Autodesk Fusion 360 part; units mm, degrees
(part 2 of 3)
sketch "Left ribbon cover release catch outline" plane through (0, 0, 1.5) normal (0, 0, 1) x (1, 0, 0) in component "02 Flat front and ribbon cover - PRINT 1"
  line L0 (84.4, -13.8) -> (85.6, -13.8)
  line L1 (85.6, -13.8) -> (85.6, -5.8)
  line L2 (85.6, -5.8) -> (86.6, -5.8)
  line L3 (86.6, -5.8) -> (86.6, -5.2)
  line L4 (86.6, -5.2) -> (85.6, -4.8)
  line L5 (85.6, -4.8) -> (84.4, -4.8)
  line L6 (84.4, -4.8) -> (84.4, -13.8)
extrude "Left ribbon cover release catch" add sketch "Left ribbon cover release catch outline" along normal blind 5 bodies 14 in component "02 Flat front and ribbon cover - PRINT 1"
ref_plane "WorkPlane30" through (0, 0, 1.5) normal (0, 0, 1) x (1, 0, 0) in component "02 Flat front and ribbon cover - PRINT 1"
sketch "Right ribbon cover release catch outline" plane through (0, 0, 1.5) normal (0, 0, 1) x (1, 0, 0) in component "02 Flat front and ribbon cover - PRINT 1"
  line L0 (129.6, -13.8) -> (128.4, -13.8)
  line L1 (128.4, -13.8) -> (128.4, -5.8)
  line L2 (128.4, -5.8) -> (127.4, -5.8)
  line L3 (127.4, -5.8) -> (127.4, -5.2)
  line L4 (127.4, -5.2) -> (128.4, -4.8)
  line L5 (128.4, -4.8) -> (129.6, -4.8)
  line L6 (129.6, -4.8) -> (129.6, -13.8)
extrude "Right ribbon cover release catch" add sketch "Right ribbon cover release catch outline" along normal blind 5 bodies 14 in component "02 Flat front and ribbon cover - PRINT 1"
ref_plane "WorkPlane31" through (0, -16.2, 0) normal (0, 1, 0) x (0, 0, 1) in component "02 Flat front and ribbon cover - PRINT 1"
sketch "Purdue Hackers official flat logo recess 1 outline" plane through (0, -16.2, 0) normal (0, 1, 0) x (1, 0, 0) in component "02 Flat front and ribbon cover - PRINT 1"
  line L0 (101.6666, -76) -> (91, -76)
  line L1 (91, -76) -> (91, -86.2945)
  line L2 (91, -86.2945) -> (101.6666, -86.2945)
  line L3 (101.6666, -86.2945) -> (101.6666, -76)
  line L4 (101.6666, -76) -> (101.6666, -76)
extrude "Purdue Hackers official flat logo recess 1" cut sketch "Purdue Hackers official flat logo recess 1 outline" along normal blind 0.6 bodies 14 in component "02 Flat front and ribbon cover - PRINT 1"
ref_plane "WorkPlane32" through (0, -16.2, 0) normal (0, 1, 0) x (0, 0, 1) in component "02 Flat front and ribbon cover - PRINT 1"
sketch "Purdue Hackers official flat logo recess 2 outline" plane through (0, -16.2, 0) normal (0, 1, 0) x (1, 0, 0) in component "02 Flat front and ribbon cover - PRINT 1"
  line L0 (112.3334, -96.5892) -> (123, -96.5892)
  line L1 (123, -96.5892) -> (123, -76)
  line L2 (123, -76) -> (112.3334, -76)
  line L3 (112.3334, -76) -> (112.3334, -86.2945)
  line L4 (112.3334, -86.2945) -> (101.6666, -86.2945)
  line L5 (101.6666, -86.2945) -> (101.6666, -106.8837)
  line L6 (101.6666, -106.8837) -> (112.3334, -106.8837)
  line L7 (112.3334, -106.8837) -> (112.3334, -96.5892)
  line L8 (112.3334, -96.5892) -> (112.3334, -96.5892)
extrude "Purdue Hackers official flat logo recess 2" cut sketch "Purdue Hackers official flat logo recess 2 outline" along normal blind 0.6 bodies 14 in component "02 Flat front and ribbon cover - PRINT 1"
ref_plane "WorkPlane33" through (0, -16.2, 0) normal (0, 1, 0) x (0, 0, 1) in component "02 Flat front and ribbon cover - PRINT 1"
sketch "Logo corner separation for manifold print outline" plane through (0, -16.2, 0) normal (0, 1, 0) x (1, 0, 0) in component "02 Flat front and ribbon cover - PRINT 1"
  line L0 (101.6666, -86.2945) -> (101.2666, -86.2945)
  line L1 (101.2666, -86.2945) -> (101.6666, -85.8945)
  line L2 (101.6666, -85.8945) -> (101.6666, -86.2945)
extrude "Logo corner separation for manifold print" add sketch "Logo corner separation for manifold print outline" along normal blind 0.6 bodies 14 in component "02 Flat front and ribbon cover - PRINT 1"
ref_plane "WorkPlane36" through (0, 0, -9) normal (0, 0, 1) x (1, 0, 0) in component "01 Electronics case - PRINT 1"
sketch "7 mm retaining hook thickness 25 outline" plane through (0, 0, -9) normal (0, 0, 1) x (1, 0, 0) in component "01 Electronics case - PRINT 1"
  line L0 (12, -11) -> (38, -11)
  line L1 (38, -11) -> (38, 45)
  line L2 (38, 45) -> (12, 45)
  line L3 (12, 45) -> (12, -11)
extrude "7 mm retaining hook thickness 25" add sketch "7 mm retaining hook thickness 25 outline" along normal blind 2 bodies 13 in component "01 Electronics case - PRINT 1"
ref_plane "WorkPlane37" through (0, 0, -9) normal (0, 0, 1) x (1, 0, 0) in component "01 Electronics case - PRINT 1"
sketch "7 mm retaining hook thickness 189 outline" plane through (0, 0, -9) normal (0, 0, 1) x (1, 0, 0) in component "01 Electronics case - PRINT 1"
  line L0 (176, -11) -> (202, -11)
  line L1 (202, -11) -> (202, 45)
  line L2 (202, 45) -> (176, 45)
  line L3 (176, 45) -> (176, -11)
extrude "7 mm retaining hook thickness 189" add sketch "7 mm retaining hook thickness 189 outline" along normal blind 2 bodies 13 in component "01 Electronics case - PRINT 1"
fillet "Rounded retaining arm upper roots" radius 1.5 4 edges at (189, -11, 65) (25, -11, 65) (189, -6, 65) (25, -6, 65) on bodies 13 in component "01 Electronics case - PRINT 1"
fillet "Rounded retaining arm inner knees" radius 1.5 4 edges at (25, -6, 7) (189, -6, 7) (189, -1, -2) (25, -1, -2) on bodies 13 in component "01 Electronics case - PRINT 1"
fillet "Rounded retaining arm outside heels" radius 2 2 edges at (25, -11, -9) (189, -11, -9) on bodies 13 in component "01 Electronics case - PRINT 1"
fillet "Lower service cover clip root relief" radius 0.6 4 edges at (159, -14.2, 71.75) (55, -14.2, 71.75) (159, -14.2, 72.95) (55, -14.2, 72.95) on bodies 14 in component "02 Flat front and ribbon cover - PRINT 1"
fillet "Upper service cover clip root relief" radius 0.4 4 edges at (159, -14.2, 163.45) (55, -14.2, 163.45) (159, -14.2, 164.25) (55, -14.2, 164.25) on bodies 14 in component "02 Flat front and ribbon cover - PRINT 1"
ref_plane "WorkPlane38" through (0, 15.6, 0) normal (0, 1, 0) x (0, 0, 1) in component "01 Electronics case - PRINT 1"
sketch "Pi screw entry relief - 0.2 mm deep layout" plane through (0, 15.6, 0) normal (0, 1, 0) x (1, 0, 0) in component "01 Electronics case - PRINT 1"
  circle A0 centre (149.5, -78.5) radius 1.4
  circle A1 centre (198.5, -78.5) radius 1.4
  circle A2 centre (149.5, -136.5) radius 1.4
  circle A3 centre (198.5, -136.5) radius 1.4
extrude "Pi screw entry relief - 0.2 mm deep" cut sketch "Pi screw entry relief - 0.2 mm deep layout" along normal blind 0.2 bodies 13 in component "01 Electronics case - PRINT 1"
ref_plane "WorkPlane39" through (0, 0, -13.5) normal (0, 0, 1) x (1, 0, 0) in component "01 Electronics case - PRINT 1"
sketch "Camera screw entry relief - 0.2 mm deep layout" plane through (0, 0, -13.5) normal (0, 0, 1) x (1, 0, 0) in component "01 Electronics case - PRINT 1"
  circle A0 centre (117.5, -7.15) radius 1.1
  circle A1 centre (117.5, 6.35) radius 1.1
  circle A2 centre (96.5, -7.15) radius 1.1
  circle A3 centre (96.5, 6.35) radius 1.1
extrude "Camera screw entry relief - 0.2 mm deep" cut sketch "Camera screw entry relief - 0.2 mm deep layout" along normal blind 0.2 bodies 13 in component "01 Electronics case - PRINT 1"
ref_plane "WorkPlane40" through (0, 0, -50) normal (0, 0, 1) x (1, 0, 0) in component "01 Electronics case - PRINT 1"
sketch "Remove integral mount below case floor outline" plane through (0, 0, -50) normal (0, 0, 1) x (1, 0, 0) in component "01 Electronics case - PRINT 1"
  line L0 (-2, -30) -> (216, -30)
  line L1 (216, -30) -> (216, 50)
  line L2 (216, 50) -> (-2, 50)
  line L3 (-2, 50) -> (-2, -30)
extrude "Remove integral mount below case floor" cut sketch "Remove integral mount below case floor outline" along normal blind 119 bodies 13 in component "01 Electronics case - PRINT 1"
ref_plane "WorkPlane41" through (0, 0, 69) normal (0, 0, 1) x (1, 0, 0) in component "01 Electronics case - PRINT 1"
sketch "Restore flat mounting floor 25 outline" plane through (0, 0, 69) normal (0, 0, 1) x (1, 0, 0) in component "01 Electronics case - PRINT 1"
  line L0 (15, 13) -> (35, 13)
  line L1 (35, 13) -> (35, 22)
  line L2 (35, 22) -> (15, 22)
  line L3 (15, 22) -> (15, 13)
extrude "Restore flat mounting floor 25" add sketch "Restore flat mounting floor 25 outline" along normal blind 0.5 bodies 13 in component "01 Electronics case - PRINT 1"
ref_plane "WorkPlane42" through (0, 0, 69) normal (0, 0, 1) x (1, 0, 0) in component "01 Electronics case - PRINT 1"
sketch "Restore flat mounting floor 189 outline" plane through (0, 0, 69) normal (0, 0, 1) x (1, 0, 0) in component "01 Electronics case - PRINT 1"
  line L0 (179, 13) -> (199, 13)
  line L1 (199, 13) -> (199, 22)
  line L2 (199, 22) -> (179, 22)
  line L3 (179, 22) -> (179, 13)
extrude "Restore flat mounting floor 189" add sketch "Restore flat mounting floor 189 outline" along normal blind 0.5 bodies 13 in component "01 Electronics case - PRINT 1"
ref_plane "WorkPlane43" through (0, 0, 71.4) normal (0, 0, 1) x (1, 0, 0) in component "01 Electronics case - PRINT 1"
sketch "Remove obsolete camera-root stub outline" plane through (0, 0, 71.4) normal (0, 0, 1) x (1, 0, 0) in component "01 Electronics case - PRINT 1"
  line L0 (85.99, -11.01) -> (128.01, -11.01)
  line L1 (128.01, -11.01) -> (128.01, -4.99)
  line L2 (128.01, -4.99) -> (85.99, -4.99)
  line L3 (85.99, -4.99) -> (85.99, -11.01)
extrude "Remove obsolete camera-root stub" cut sketch "Remove obsolete camera-root stub outline" along normal blind 0.71 bodies 13 in component "01 Electronics case - PRINT 1"
ref_plane "WorkPlane44" through (0, 0, 68.9) normal (0, 0, 1) x (1, 0, 0) in component "01 Electronics case - PRINT 1"
sketch "Six M3 bench assembly clearance holes layout" plane through (0, 0, 68.9) normal (0, 0, 1) x (1, 0, 0) in component "01 Electronics case - PRINT 1"
  circle A0 centre (18, 16) radius 1.7
  circle A1 centre (32, 16) radius 1.7
  circle A2 centre (182, 16) radius 1.7
  circle A3 centre (196, 16) radius 1.7
  circle A4 centre (92, -2.5) radius 1.7
  circle A5 centre (122, -2.5) radius 1.7
extrude "Six M3 bench assembly clearance holes" cut sketch "Six M3 bench assembly clearance holes layout" along normal blind 2.6 bodies 13 in component "01 Electronics case - PRINT 1"
ref_plane "WorkPlane45" through (0, 0, 75) normal (0, 0, 1) x (1, 0, 0) in component "01 Electronics case - PRINT 1"
sketch "Battery port open to front edge outline" plane through (0, 0, 75) normal (0, 0, 1) x (1, 0, 0) in component "01 Electronics case - PRINT 1"
  line L0 (-1, -14.1) -> (3.2, -14.1)
  line L1 (3.2, -14.1) -> (3.2, 20.5)
  line L2 (3.2, 20.5) -> (-1, 20.5)
  line L3 (-1, 20.5) -> (-1, -14.1)
extrude "Battery port open to front edge" cut sketch "Battery port open to front edge outline" along normal blind 77 bodies 13 in component "01 Electronics case - PRINT 1"
ref_plane "WorkPlane46" through (0, 0, 77) normal (0, 0, 1) x (1, 0, 0) in component "01 Electronics case - PRINT 1"
sketch "Pi side ports open to front edge outline" plane through (0, 0, 77) normal (0, 0, 1) x (1, 0, 0) in component "01 Electronics case - PRINT 1"
  line L0 (210.8, -14.1) -> (215, -14.1)
  line L1 (215, -14.1) -> (215, 18)
  line L2 (215, 18) -> (210.8, 18)
  line L3 (210.8, 18) -> (210.8, -14.1)
extrude "Pi side ports open to front edge" cut sketch "Pi side ports open to front edge outline" along normal blind 60 bodies 13 in component "01 Electronics case - PRINT 1"
ref_plane "WorkPlane47" through (0, 0, 164.5) normal (0, 0, 1) x (1, 0, 0) in component "01 Electronics case - PRINT 1"
sketch "Pi top ports open to front edge outline" plane through (0, 0, 164.5) normal (0, 0, 1) x (1, 0, 0) in component "01 Electronics case - PRINT 1"
  line L0 (144, -14.1) -> (203, -14.1)
  line L1 (203, -14.1) -> (203, 17)
  line L2 (203, 17) -> (144, 17)
  line L3 (144, 17) -> (144, -14.1)
extrude "Pi top ports open to front edge" cut sketch "Pi top ports open to front edge outline" along normal blind 2.6 bodies 13 in component "01 Electronics case - PRINT 1"
ref_plane "WorkPlane48" through (0, 0, 164.5) normal (0, 0, 1) x (1, 0, 0) in component "01 Electronics case - PRINT 1"
sketch "Relocated upper-right cover latch outline" plane through (0, 0, 164.5) normal (0, 0, 1) x (1, 0, 0) in component "01 Electronics case - PRINT 1"
  line L0 (205, -10) -> (211, -10)
  line L1 (211, -10) -> (211, -5.5)
  line L2 (211, -5.5) -> (205, -5.5)
  line L3 (205, -5.5) -> (205, -10)
extrude "Relocated upper-right cover latch" cut sketch "Relocated upper-right cover latch outline" along normal blind 2.6 bodies 13 in component "01 Electronics case - PRINT 1"
ref_plane "WorkPlane49" through (0, 0, 161) normal (0, 0, 1) x (1, 0, 0) in component "01 Electronics case - PRINT 1"
sketch "Reinforced 6 mm roof tether bridge outline" plane through (0, 0, 161) normal (0, 0, 1) x (1, 0, 0) in component "01 Electronics case - PRINT 1"
  line L0 (96, -4) -> (120, -4)
  line L1 (120, -4) -> (120, 14)
  line L2 (120, 14) -> (96, 14)
  line L3 (96, 14) -> (96, -4)
extrude "Reinforced 6 mm roof tether bridge" add sketch "Reinforced 6 mm roof tether bridge outline" along normal blind 6 bodies 13 in component "01 Electronics case - PRINT 1"
ref_plane "WorkPlane50" through (0, 0, 160.9) normal (0, 0, 1) x (1, 0, 0) in component "01 Electronics case - PRINT 1"
sketch "Two accessible roof tether slots layout" plane through (0, 0, 160.9) normal (0, 0, 1) x (1, 0, 0) in component "01 Electronics case - PRINT 1"
  line L0 (99, 1) -> (104, 1)
  line L1 (104, 1) -> (104, 8)
  line L2 (104, 8) -> (99, 8)
  line L3 (99, 8) -> (99, 1)
  line L4 (112, 1) -> (117, 1)
  line L5 (117, 1) -> (117, 8)
  line L6 (117, 8) -> (112, 8)
  line L7 (112, 8) -> (112, 1)
extrude "Two accessible roof tether slots" cut sketch "Two accessible roof tether slots layout" along normal blind 6.2 bodies 13 in component "01 Electronics case - PRINT 1"
ref_plane "WorkPlane34" through (0, 0, -12.5) normal (0, 0, 1) x (1, 0, 0) in component "02 Flat front and ribbon cover - PRINT 1"
sketch "Continuous flat ribbon-cover exterior outline" plane through (0, 0, -12.5) normal (0, 0, 1) x (1, 0, 0) in component "02 Flat front and ribbon cover - PRINT 1"
  line L0 (96, -16.2) -> (118, -16.2)
  line L1 (118, -16.2) -> (118, -12.6)
  line L2 (118, -12.6) -> (96, -12.6)
  line L3 (96, -12.6) -> (96, -16.2)
extrude "Continuous flat ribbon-cover exterior" add sketch "Continuous flat ribbon-cover exterior outline" along normal blind 86.8 bodies 14 in component "02 Flat front and ribbon cover - PRINT 1"
ref_plane "WorkPlane35" through (0, 0, 1) normal (0, 0, 1) x (1, 0, 0) in component "02 Flat front and ribbon cover - PRINT 1"
sketch "Flat base beneath lower release bridge outline" plane through (0, 0, 1) normal (0, 0, 1) x (1, 0, 0) in component "02 Flat front and ribbon cover - PRINT 1"
  line L0 (84.4, -16.2) -> (129.6, -16.2)
  line L1 (129.6, -16.2) -> (129.6, -12.6)
  line L2 (129.6, -12.6) -> (84.4, -12.6)
  line L3 (84.4, -12.6) -> (84.4, -16.2)
extrude "Flat base beneath lower release bridge" add sketch "Flat base beneath lower release bridge outline" along normal blind 6 bodies 14 in component "02 Flat front and ribbon cover - PRINT 1"
ref_plane "WorkPlane36" through (0, 0, -12.5) normal (0, 0, 1) x (1, 0, 0) in component "02 Flat front and ribbon cover - PRINT 1"
sketch "Extend ribbon edge flange 96 outline" plane through (0, 0, -12.5) normal (0, 0, 1) x (1, 0, 0) in component "02 Flat front and ribbon cover - PRINT 1"
  line L0 (96, -12.6) -> (98, -12.6)
  line L1 (98, -12.6) -> (98, -11.2)
  line L2 (98, -11.2) -> (96, -11.2)
  line L3 (96, -11.2) -> (96, -12.6)
extrude "Extend ribbon edge flange 96" add sketch "Extend ribbon edge flange 96 outline" along normal blind 8.6 bodies 14 in component "02 Flat front and ribbon cover - PRINT 1"
ref_plane "WorkPlane37" through (0, 0, -12.5) normal (0, 0, 1) x (1, 0, 0) in component "02 Flat front and ribbon cover - PRINT 1"
sketch "Extend ribbon edge flange 116 outline" plane through (0, 0, -12.5) normal (0, 0, 1) x (1, 0, 0) in component "02 Flat front and ribbon cover - PRINT 1"
  line L0 (116, -12.6) -> (118, -12.6)
  line L1 (118, -12.6) -> (118, -11.2)
  line L2 (118, -11.2) -> (116, -11.2)
  line L3 (116, -11.2) -> (116, -12.6)
extrude "Extend ribbon edge flange 116" add sketch "Extend ribbon edge flange 116 outline" along normal blind 8.6 bodies 14 in component "02 Flat front and ribbon cover - PRINT 1"
ref_plane "WorkPlane38" through (0, 0, 162.9) normal (0, 0, 1) x (1, 0, 0) in component "02 Flat front and ribbon cover - PRINT 1"
sketch "Remove old top snap over USB opening outline" plane through (0, 0, 162.9) normal (0, 0, 1) x (1, 0, 0) in component "02 Flat front and ribbon cover - PRINT 1"
  line L0 (156, -14.2) -> (162, -14.2)
  line L1 (162, -14.2) -> (162, -5.5)
  line L2 (162, -5.5) -> (156, -5.5)
  line L3 (156, -5.5) -> (156, -14.2)
extrude "Remove old top snap over USB opening" cut sketch "Remove old top snap over USB opening outline" along normal blind 2.5 bodies 14 in component "02 Flat front and ribbon cover - PRINT 1"
ref_plane "WorkPlane39" through (205.5, 0, 0) normal (1, 0, 0) x (0, 1, 0) in component "02 Flat front and ribbon cover - PRINT 1"
sketch "Relocated upper-right snap clear of ports outline" plane through (205.5, 0, 0) normal (1, 0, 0) x (0, 0, -1) in component "02 Flat front and ribbon cover - PRINT 1"
  line L0 (-163.45, -14.2) -> (-164.25, -14.2)
  line L1 (-164.25, -14.2) -> (-164.25, -9)
  line L2 (-164.25, -9) -> (-165.2, -9)
  line L3 (-165.2, -9) -> (-165.2, -8.2)
  line L4 (-165.2, -8.2) -> (-164.25, -6.8)
  line L5 (-164.25, -6.8) -> (-163.45, -6.8)
  line L6 (-163.45, -6.8) -> (-163.45, -14.2)
extrude "Relocated upper-right snap clear of ports" add sketch "Relocated upper-right snap clear of ports outline" along normal blind 5 bodies 14 in component "02 Flat front and ribbon cover - PRINT 1"
fillet "Relocated snap rounded roots" radius 0.4 2 edges at (208, -14.2, 163.45) (208, -14.2, 164.25) on bodies 14 in component "02 Flat front and ribbon cover - PRINT 1"
ref_plane "WorkPlane1" through (0, 0, -6) normal (0, 0, 1) x (1, 0, 0) in component "04 Downward camera carrier - PRINT 1"
sketch "Camera spine outline" plane through (0, 0, -6) normal (0, 0, 1) x (1, 0, 0) in component "04 Downward camera carrier - PRINT 1"
  line L0 (86, -11) -> (128, -11)
  line L1 (128, -11) -> (128, -6)
  line L2 (128, -6) -> (86, -6)
  line L3 (86, -6) -> (86, -11)
extrude "Camera spine" add sketch "Camera spine outline" along normal blind 83.5 separate body makes body 15 in component "04 Downward camera carrier - PRINT 1"
ref_plane "WorkPlane2" through (0, 0, 69.5) normal (0, 0, 1) x (1, 0, 0) in component "04 Downward camera carrier - PRINT 1"
sketch "Bench attachment shelf outline" plane through (0, 0, 69.5) normal (0, 0, 1) x (1, 0, 0) in component "04 Downward camera carrier - PRINT 1"
  line L0 (86, -11) -> (128, -11)
  line L1 (128, -11) -> (128, 4)
  line L2 (128, 4) -> (86, 4)
  line L3 (86, 4) -> (86, -11)
extrude "Bench attachment shelf" add sketch "Bench attachment shelf outline" along normal blind 8 bodies 15 in component "04 Downward camera carrier - PRINT 1"
ref_plane "WorkPlane3" through (0, 0, -10) normal (0, 0, 1) x (1, 0, 0) in component "04 Downward camera carrier - PRINT 1"
sketch "Camera backplate outline" plane through (0, 0, -10) normal (0, 0, 1) x (1, 0, 0) in component "04 Downward camera carrier - PRINT 1"
  line L0 (86, -23.65) -> (128, -23.65)
  line L1 (128, -23.65) -> (128, 18.35)
  line L2 (128, 18.35) -> (86, 18.35)
  line L3 (86, 18.35) -> (86, -23.65)
extrude "Camera backplate" add sketch "Camera backplate outline" along normal blind 4 bodies 15 in component "04 Downward camera carrier - PRINT 1"
ref_plane "WorkPlane4" through (0, -10.35, 0) normal (0, 1, 0) x (0, 0, 1) in component "04 Downward camera carrier - PRINT 1"
sketch "45 degree camera screw support (96.5, -7.15) outline" plane through (0, -10.35, 0) normal (0, 1, 0) x (1, 0, 0) in component "04 Downward camera carrier - PRINT 1"
  line L0 (89.8, 10) -> (93.3, 13.5)
  line L1 (93.3, 13.5) -> (99.7, 13.5)
  line L2 (99.7, 13.5) -> (99.7, 10)
  line L3 (99.7, 10) -> (89.8, 10)
extrude "45 degree camera screw support (96.5, -7.15)" add sketch "45 degree camera screw support (96.5, -7.15) outline" along normal blind 6.4 bodies 15 in component "04 Downward camera carrier - PRINT 1"
ref_plane "WorkPlane5" through (0, 3.15, 0) normal (0, 1, 0) x (0, 0, 1) in component "04 Downward camera carrier - PRINT 1"
sketch "45 degree camera screw support (96.5, 6.35) outline" plane through (0, 3.15, 0) normal (0, 1, 0) x (1, 0, 0) in component "04 Downward camera carrier - PRINT 1"
  line L0 (89.8, 10) -> (93.3, 13.5)
  line L1 (93.3, 13.5) -> (99.7, 13.5)
  line L2 (99.7, 13.5) -> (99.7, 10)
  line L3 (99.7, 10) -> (89.8, 10)
extrude "45 degree camera screw support (96.5, 6.35)" add sketch "45 degree camera screw support (96.5, 6.35) outline" along normal blind 6.4 bodies 15 in component "04 Downward camera carrier - PRINT 1"
ref_plane "WorkPlane6" through (0, -10.35, 0) normal (0, 1, 0) x (0, 0, 1) in component "04 Downward camera carrier - PRINT 1"
sketch "45 degree camera screw support (117.5, -7.15) outline" plane through (0, -10.35, 0) normal (0, 1, 0) x (1, 0, 0) in component "04 Downward camera carrier - PRINT 1"
  line L0 (110.8, 10) -> (114.3, 13.5)
  line L1 (114.3, 13.5) -> (120.7, 13.5)
  line L2 (120.7, 13.5) -> (120.7, 10)
  line L3 (120.7, 10) -> (110.8, 10)
extrude "45 degree camera screw support (117.5, -7.15)" add sketch "45 degree camera screw support (117.5, -7.15) outline" along normal blind 6.4 bodies 15 in component "04 Downward camera carrier - PRINT 1"
ref_plane "WorkPlane7" through (0, 3.15, 0) normal (0, 1, 0) x (0, 0, 1) in component "04 Downward camera carrier - PRINT 1"
sketch "45 degree camera screw support (117.5, 6.35) outline" plane through (0, 3.15, 0) normal (0, 1, 0) x (1, 0, 0) in component "04 Downward camera carrier - PRINT 1"
  line L0 (110.8, 10) -> (114.3, 13.5)
  line L1 (114.3, 13.5) -> (120.7, 13.5)
  line L2 (120.7, 13.5) -> (120.7, 10)
  line L3 (120.7, 10) -> (110.8, 10)
extrude "45 degree camera screw support (117.5, 6.35)" add sketch "45 degree camera screw support (117.5, 6.35) outline" along normal blind 6.4 bodies 15 in component "04 Downward camera carrier - PRINT 1"
ref_plane "WorkPlane8" through (0, 0, -13.5) normal (0, 0, 1) x (1, 0, 0) in component "04 Downward camera carrier - PRINT 1"
sketch "M2 direct screw pilots layout" plane through (0, 0, -13.5) normal (0, 0, 1) x (1, 0, 0) in component "04 Downward camera carrier - PRINT 1"
  circle A0 centre (96.5, -7.15) radius 0.85
  circle A1 centre (96.5, 6.35) radius 0.85
  circle A2 centre (117.5, -7.15) radius 0.85
  circle A3 centre (117.5, 6.35) radius 0.85
extrude "M2 direct screw pilots" cut sketch "M2 direct screw pilots layout" along normal blind 4 bodies 15 in component "04 Downward camera carrier - PRINT 1"
ref_plane "WorkPlane9" through (0, 0, -13.5) normal (0, 0, 1) x (1, 0, 0) in component "04 Downward camera carrier - PRINT 1"
sketch "M2 screw entry relief layout" plane through (0, 0, -13.5) normal (0, 0, 1) x (1, 0, 0) in component "04 Downward camera carrier - PRINT 1"
  circle A0 centre (96.5, -7.15) radius 1.1
  circle A1 centre (96.5, 6.35) radius 1.1
  circle A2 centre (117.5, -7.15) radius 1.1
  circle A3 centre (117.5, 6.35) radius 1.1
extrude "M2 screw entry relief" cut sketch "M2 screw entry relief layout" along normal blind 0.2 bodies 15 in component "04 Downward camera carrier - PRINT 1"
ref_plane "WorkPlane10" through (0, 0, -6) normal (0, 0, 1) x (1, 0, 0) in component "04 Downward camera carrier - PRINT 1"
sketch "Recessed ribbon channel outline (2)" plane through (0, 0, -6) normal (0, 0, 1) x (1, 0, 0) in component "04 Downward camera carrier - PRINT 1"
  line L0 (98, -11.1) -> (116, -11.1)
  line L1 (116, -11.1) -> (116, -9.4)
  line L2 (116, -9.4) -> (98, -9.4)
  line L3 (98, -9.4) -> (98, -11.1)
extrude "Recessed ribbon channel'" cut sketch "Recessed ribbon channel outline (2)" along normal blind 83.6 bodies 15 in component "04 Downward camera carrier - PRINT 1"
ref_plane "WorkPlane11" through (0, 0, -10.1) normal (0, 0, 1) x (1, 0, 0) in component "04 Downward camera carrier - PRINT 1"
sketch "Ribbon turn with 45 degree printed roof outline" plane through (0, 0, -10.1) normal (0, 0, 1) x (1, 0, 0) in component "04 Downward camera carrier - PRINT 1"
  line L0 (98, -24) -> (128.5, -24)
  line L1 (128.5, -24) -> (116, -11.5)
  line L2 (116, -11.5) -> (98, -11.5)
  line L3 (98, -11.5) -> (98, -24)
extrude "Ribbon turn with 45 degree printed roof" cut sketch "Ribbon turn with 45 degree printed roof outline" along normal blind 4.2 bodies 15 in component "04 Downward camera carrier - PRINT 1"
ref_plane "WorkPlane12" through (0, 0, 69.4) normal (0, 0, 1) x (1, 0, 0) in component "04 Downward camera carrier - PRINT 1"
sketch "Camera shelf M3 clearance layout" plane through (0, 0, 69.4) normal (0, 0, 1) x (1, 0, 0) in component "04 Downward camera carrier - PRINT 1"
  circle A0 centre (92, -2.5) radius 1.7
  circle A1 centre (122, -2.5) radius 1.7
extrude "Camera shelf M3 clearance" cut sketch "Camera shelf M3 clearance layout" along normal blind 8.2 bodies 15 in component "04 Downward camera carrier - PRINT 1"
ref_plane "WorkPlane13" through (0, 0, 69.4) normal (0, 0, 1) x (1, 0, 0) in component "04 Downward camera carrier - PRINT 1"
sketch "Camera shelf captive M3 nut 92 outline" plane through (0, 0, 69.4) normal (0, 0, 1) x (1, 0, 0) in component "04 Downward camera carrier - PRINT 1"
  line L0 (95.3486, -2.5) -> (93.6743, 0.4)
  line L1 (93.6743, 0.4) -> (90.3257, 0.4)
  line L2 (90.3257, 0.4) -> (88.6514, -2.5)
  line L3 (88.6514, -2.5) -> (90.3257, -5.4)
  line L4 (90.3257, -5.4) -> (93.6743, -5.4)
  line L5 (93.6743, -5.4) -> (95.3486, -2.5)
extrude "Camera shelf captive M3 nut 92" cut sketch "Camera shelf captive M3 nut 92 outline" along normal blind 4.1 bodies 15 in component "04 Downward camera carrier - PRINT 1"
ref_plane "WorkPlane14" through (0, 0, 69.4) normal (0, 0, 1) x (1, 0, 0) in component "04 Downward camera carrier - PRINT 1"
sketch "Camera shelf captive M3 nut 122 outline" plane through (0, 0, 69.4) normal (0, 0, 1) x (1, 0, 0) in component "04 Downward camera carrier - PRINT 1"
  line L0 (125.3486, -2.5) -> (123.6743, 0.4)
  line L1 (123.6743, 0.4) -> (120.3257, 0.4)
  line L2 (120.3257, 0.4) -> (118.6514, -2.5)
  line L3 (118.6514, -2.5) -> (120.3257, -5.4)
  line L4 (120.3257, -5.4) -> (123.6743, -5.4)
  line L5 (123.6743, -5.4) -> (125.3486, -2.5)
extrude "Camera shelf captive M3 nut 122" cut sketch "Camera shelf captive M3 nut 122 outline" along normal blind 4.1 bodies 15 in component "04 Downward camera carrier - PRINT 1"
ref_plane "WorkPlane15" through (0, 0, -9) normal (0, 0, 1) x (1, 0, 0) in component "04 Downward camera carrier - PRINT 1"
sketch "L camera guard latch pocket outline (2)" plane through (0, 0, -9) normal (0, 0, 1) x (1, 0, 0) in component "04 Downward camera carrier - PRINT 1"
  line L0 (85.9, -3.4) -> (87.1, -3.4)
  line L1 (87.1, -3.4) -> (87.1, 3.4)
  line L2 (87.1, 3.4) -> (85.9, 3.4)
  line L3 (85.9, 3.4) -> (85.9, -3.4)
extrude "L camera guard latch pocket'" cut sketch "L camera guard latch pocket outline (2)" along normal blind 3.1 bodies 15 in component "04 Downward camera carrier - PRINT 1"
ref_plane "WorkPlane16" through (0, 0, -9) normal (0, 0, 1) x (1, 0, 0) in component "04 Downward camera carrier - PRINT 1"
sketch "R camera guard latch pocket outline (2)" plane through (0, 0, -9) normal (0, 0, 1) x (1, 0, 0) in component "04 Downward camera carrier - PRINT 1"
  line L0 (126.9, -3.4) -> (128.1, -3.4)
  line L1 (128.1, -3.4) -> (128.1, 3.4)
  line L2 (128.1, 3.4) -> (126.9, 3.4)
  line L3 (126.9, 3.4) -> (126.9, -3.4)
extrude "R camera guard latch pocket'" cut sketch "R camera guard latch pocket outline (2)" along normal blind 3.1 bodies 15 in component "04 Downward camera carrier - PRINT 1"
ref_plane "WorkPlane1" through (-13, 0, 0) normal (1, 0, 0) x (0, 1, 0) in component "05 Adjustable C clamp - PRINT 2"
sketch "10 mm web and 12 mm lower jaw outline" plane through (-13, 0, 0) normal (1, 0, 0) x (0, 0, -1) in component "05 Adjustable C clamp - PRINT 2"
  line L0 (24, -14) -> (24, 31)
  line L1 (24, 31) -> (12, 31)
  line L2 (12, 31) -> (12, -4)
  line L3 (12, -4) -> (-57.5, -4)
  line L4 (-57.5, -4) -> (-57.5, 11.5)
  line L5 (-57.5, 11.5) -> (-69.5, 11.5)
  line L6 (-69.5, 11.5) -> (-69.5, 22.4)
  line L7 (-69.5, 22.4) -> (-77.5, 22.4)
  line L8 (-77.5, 22.4) -> (-77.5, -14)
  line L9 (-77.5, -14) -> (24, -14)
extrude "10 mm web and 12 mm lower jaw" add sketch "10 mm web and 12 mm lower jaw outline" along normal blind 26 separate body makes body 16 in component "05 Adjustable C clamp - PRINT 2"
fillet "4 mm upper and lower inner roots" radius 4 2 edges at (0, -4, -12) (0, -4, 57.5) on bodies 16 in component "05 Adjustable C clamp - PRINT 2"
fillet "2 mm outer clamp corners" radius 2 4 edges at (0, -14, -24) (0, -14, 77.5) (0, 31, -24) (0, 31, -12) on bodies 16 in component "05 Adjustable C clamp - PRINT 2"
ref_plane "WorkPlane2" through (0, 0, -24.1) normal (0, 0, 1) x (1, 0, 0) in component "05 Adjustable C clamp - PRINT 2"
sketch "M5 sliding screw clearance layout" plane through (0, 0, -24.1) normal (0, 0, 1) x (1, 0, 0) in component "05 Adjustable C clamp - PRINT 2"
  circle A0 centre (0, 17.5) radius 2.8
extrude "M5 sliding screw clearance" cut sketch "M5 sliding screw clearance layout" along normal blind 12.2 bodies 16 in component "05 Adjustable C clamp - PRINT 2"
ref_plane "WorkPlane3" through (0, 0, -24.1) normal (0, 0, 1) x (1, 0, 0) in component "05 Adjustable C clamp - PRINT 2"
sketch "Captive DIN 934 M5 nut pocket outline" plane through (0, 0, -24.1) normal (0, 0, 1) x (1, 0, 0) in component "05 Adjustable C clamp - PRINT 2"
  line L0 (4.792, 17.5) -> (2.396, 21.65)
  line L1 (2.396, 21.65) -> (-2.396, 21.65)
  line L2 (-2.396, 21.65) -> (-4.792, 17.5)
  line L3 (-4.792, 17.5) -> (-2.396, 13.35)
  line L4 (-2.396, 13.35) -> (2.396, 13.35)
  line L5 (2.396, 13.35) -> (4.792, 17.5)
extrude "Captive DIN 934 M5 nut pocket" cut sketch "Captive DIN 934 M5 nut pocket outline" along normal blind 4.4 bodies 16 in component "05 Adjustable C clamp - PRINT 2"
ref_plane "WorkPlane4" through (0, 0, 69.4) normal (0, 0, 1) x (1, 0, 0) in component "05 Adjustable C clamp - PRINT 2"
sketch "Two M3 shelf fasteners layout" plane through (0, 0, 69.4) normal (0, 0, 1) x (1, 0, 0) in component "05 Adjustable C clamp - PRINT 2"
  circle A0 centre (-7, 16) radius 1.7
  circle A1 centre (7, 16) radius 1.7
extrude "Two M3 shelf fasteners" cut sketch "Two M3 shelf fasteners layout" along normal blind 8.2 bodies 16 in component "05 Adjustable C clamp - PRINT 2"
ref_plane "WorkPlane5" through (0, 0, 69.4) normal (0, 0, 1) x (1, 0, 0) in component "05 Adjustable C clamp - PRINT 2"
sketch "Captive shelf M3 nut -7 outline" plane through (0, 0, 69.4) normal (0, 0, 1) x (1, 0, 0) in component "05 Adjustable C clamp - PRINT 2"
  line L0 (-3.6514, 16) -> (-5.3257, 18.9)
  line L1 (-5.3257, 18.9) -> (-8.6743, 18.9)
  line L2 (-8.6743, 18.9) -> (-10.3486, 16)
  line L3 (-10.3486, 16) -> (-8.6743, 13.1)
  line L4 (-8.6743, 13.1) -> (-5.3257, 13.1)
  line L5 (-5.3257, 13.1) -> (-3.6514, 16)
extrude "Captive shelf M3 nut -7" cut sketch "Captive shelf M3 nut -7 outline" along normal blind 4.1 bodies 16 in component "05 Adjustable C clamp - PRINT 2"
ref_plane "WorkPlane6" through (0, 0, 69.4) normal (0, 0, 1) x (1, 0, 0) in component "05 Adjustable C clamp - PRINT 2"
sketch "Captive shelf M3 nut 7 outline" plane through (0, 0, 69.4) normal (0, 0, 1) x (1, 0, 0) in component "05 Adjustable C clamp - PRINT 2"
  line L0 (10.3486, 16) -> (8.6743, 18.9)
  line L1 (8.6743, 18.9) -> (5.3257, 18.9)
  line L2 (5.3257, 18.9) -> (3.6514, 16)
  line L3 (3.6514, 16) -> (5.3257, 13.1)
  line L4 (5.3257, 13.1) -> (8.6743, 13.1)
  line L5 (8.6743, 13.1) -> (10.3486, 16)
extrude "Captive shelf M3 nut 7" cut sketch "Captive shelf M3 nut 7 outline" along normal blind 4.1 bodies 16 in component "05 Adjustable C clamp - PRINT 2"
ref_plane "WorkPlane7" through (0, 0, -24.1) normal (0, 0, 1) x (1, 0, 0) in component "05 Adjustable C clamp - PRINT 2"
sketch "Pressure-shoe retainer tie slot layout" plane through (0, 0, -24.1) normal (0, 0, 1) x (1, 0, 0) in component "05 Adjustable C clamp - PRINT 2"
  line L0 (-3, 3) -> (3, 3)
  line L1 (3, 3) -> (3, 5.5)
  line L2 (3, 5.5) -> (-3, 5.5)
  line L3 (-3, 5.5) -> (-3, 3)
extrude "Pressure-shoe retainer tie slot" cut sketch "Pressure-shoe retainer tie slot layout" along normal blind 12.2 bodies 16 in component "05 Adjustable C clamp - PRINT 2"
ref_plane "WorkPlane1" through (0, 0, -8.5) normal (0, 0, 1) x (1, 0, 0) in component "06 Padded pressure shoe - PRINT 2"
sketch "Pressure spreader outline" plane through (0, 0, -8.5) normal (0, 0, 1) x (1, 0, 0) in component "06 Padded pressure shoe - PRINT 2"
  line L0 (-8, 9.5) -> (8, 9.5)
  line L1 (10, 11.5) -> (10, 23.5)
  line L2 (8, 25.5) -> (-8, 25.5)
  line L3 (-10, 23.5) -> (-10, 11.5)
  arc A0 (8, 9.5) -> (10, 11.5) centre (8, 11.5) ccw
  arc A1 (10, 23.5) -> (8, 25.5) centre (8, 23.5) ccw
  arc A2 (-8, 25.5) -> (-10, 23.5) centre (-8, 23.5) ccw
  arc A3 (-10, 11.5) -> (-8, 9.5) centre (-8, 11.5) ccw
extrude "Pressure spreader" add sketch "Pressure spreader outline" along normal blind 6 separate body makes body 17 in component "06 Padded pressure shoe - PRINT 2"
ref_plane "WorkPlane2" through (0, 0, -8.5) normal (0, 0, 1) x (1, 0, 0) in component "06 Padded pressure shoe - PRINT 2"
sketch "Loose retaining-tie tab outline" plane through (0, 0, -8.5) normal (0, 0, 1) x (1, 0, 0) in component "06 Padded pressure shoe - PRINT 2"
  line L0 (-4, 5.5) -> (4, 5.5)
  line L1 (4, 5.5) -> (4, 11)
  line L2 (4, 11) -> (-4, 11)
  line L3 (-4, 11) -> (-4, 5.5)
extrude "Loose retaining-tie tab" add sketch "Loose retaining-tie tab outline" along normal blind 6 bodies 17 in component "06 Padded pressure shoe - PRINT 2"
ref_plane "WorkPlane3" through (0, 0, -8.6) normal (0, 0, 1) x (1, 0, 0) in component "06 Padded pressure shoe - PRINT 2"
sketch "Retaining tie slot layout" plane through (0, 0, -8.6) normal (0, 0, 1) x (1, 0, 0) in component "06 Padded pressure shoe - PRINT 2"
  line L0 (-2.5, 7) -> (2.5, 7)
  line L1 (2.5, 7) -> (2.5, 9)
  line L2 (2.5, 9) -> (-2.5, 9)
  line L3 (-2.5, 9) -> (-2.5, 7)
extrude "Retaining tie slot" cut sketch "Retaining tie slot layout" along normal blind 6.2 bodies 17 in component "06 Padded pressure shoe - PRINT 2"
ref_plane "WorkPlane4" through (0, 0, -8.6) normal (0, 0, 1) x (1, 0, 0) in component "06 Padded pressure shoe - PRINT 2"
sketch "Blind seat for M5 screw tip layout" plane through (0, 0, -8.6) normal (0, 0, 1) x (1, 0, 0) in component "06 Padded pressure shoe - PRINT 2"
  circle A0 centre (0, 17.5) radius 2.9
extrude "Blind seat for M5 screw tip" cut sketch "Blind seat for M5 screw tip layout" along normal blind 2.1 bodies 17 in component "06 Padded pressure shoe - PRINT 2"
ref_plane "WorkPlane1" through (0, 0, -40.5) normal (0, 0, 1) x (1, 0, 0) in component "07 M5 hex bolt hand knob - PRINT 2"
sketch "28 mm hand knob layout" plane through (0, 0, -40.5) normal (0, 0, 1) x (1, 0, 0) in component "07 M5 hex bolt hand knob - PRINT 2"
  circle A0 centre (0, 17.5) radius 14
extrude "28 mm hand knob" add sketch "28 mm hand knob layout" along normal blind 9 separate body makes body 18 in component "07 M5 hex bolt hand knob - PRINT 2"
ref_plane "WorkPlane2" through (0, 0, -40.6) normal (0, 0, 1) x (1, 0, 0) in component "07 M5 hex bolt hand knob - PRINT 2"
sketch "Six finger scallops layout" plane through (0, 0, -40.6) normal (0, 0, 1) x (1, 0, 0) in component "07 M5 hex bolt hand knob - PRINT 2"
  circle A0 centre (15.5, 17.5) radius 3.5
  circle A1 centre (7.75, 30.9234) radius 3.5
  circle A2 centre (-7.75, 30.9234) radius 3.5
  circle A3 centre (-15.5, 17.5) radius 3.5
  circle A4 centre (-7.75, 4.0766) radius 3.5
  circle A5 centre (7.75, 4.0766) radius 3.5
extrude "Six finger scallops" cut sketch "Six finger scallops layout" along normal blind 9.2 bodies 18 in component "07 M5 hex bolt hand knob - PRINT 2"
ref_plane "WorkPlane3" through (0, 0, -40.6) normal (0, 0, 1) x (1, 0, 0) in component "07 M5 hex bolt hand knob - PRINT 2"
sketch "M5 shank clearance layout" plane through (0, 0, -40.6) normal (0, 0, 1) x (1, 0, 0) in component "07 M5 hex bolt hand knob - PRINT 2"
  circle A0 centre (0, 17.5) radius 2.8
extrude "M5 shank clearance" cut sketch "M5 shank clearance layout" along normal blind 9.2 bodies 18 in component "07 M5 hex bolt hand knob - PRINT 2"
ref_plane "WorkPlane4" through (0, 0, -40.6) normal (0, 0, 1) x (1, 0, 0) in component "07 M5 hex bolt hand knob - PRINT 2"
sketch "DIN 933 hex bolt head pocket outline" plane through (0, 0, -40.6) normal (0, 0, 1) x (1, 0, 0) in component "07 M5 hex bolt hand knob - PRINT 2"
  line L0 (4.792, 17.5) -> (2.396, 21.65)
  line L1 (2.396, 21.65) -> (-2.396, 21.65)
  line L2 (-2.396, 21.65) -> (-4.792, 17.5)
  line L3 (-4.792, 17.5) -> (-2.396, 13.35)
  line L4 (-2.396, 13.35) -> (2.396, 13.35)
  line L5 (2.396, 13.35) -> (4.792, 17.5)
extrude "DIN 933 hex bolt head pocket" cut sketch "DIN 933 hex bolt head pocket outline" along normal blind 4.1 bodies 18 in component "07 M5 hex bolt hand knob - PRINT 2"
ref_plane "WorkPlane1" through (0, 0, 55) normal (0, 0, 1) x (1, 0, 0) in component "REFERENCE - v11 rubber contact pads"
sketch "Lower ledge pad 25 outline" plane through (0, 0, 55) normal (0, 0, 1) x (1, 0, 0) in component "REFERENCE - v11 rubber contact pads"
  line L0 (15, 0.5) -> (35, 0.5)
  line L1 (35, 0.5) -> (35, 10.5)
  line L2 (35, 10.5) -> (15, 10.5)
  line L3 (15, 10.5) -> (15, 0.5)
extrude "Lower ledge pad 25" add sketch "Lower ledge pad 25 outline" along normal blind 2.5 separate body makes body 19 in component "REFERENCE - v11 rubber contact pads"
ref_plane "WorkPlane2" through (0, 0, 67) normal (0, 0, 1) x (1, 0, 0) in component "REFERENCE - v11 rubber contact pads"
sketch "Upper ledge pad 25 outline" plane through (0, 0, 67) normal (0, 0, 1) x (1, 0, 0) in component "REFERENCE - v11 rubber contact pads"
  line L0 (15, 13) -> (35, 13)
  line L1 (35, 13) -> (35, 22)
  line L2 (35, 22) -> (15, 22)
  line L3 (15, 22) -> (15, 13)
extrude "Upper ledge pad 25" add sketch "Upper ledge pad 25 outline" along normal blind 2.5 separate body makes body 20 in component "REFERENCE - v11 rubber contact pads"
ref_plane "WorkPlane3" through (0, 0, -2.5) normal (0, 0, 1) x (1, 0, 0) in component "REFERENCE - v11 rubber contact pads"
sketch "Moving shoe rubber pad 25 outline" plane through (0, 0, -2.5) normal (0, 0, 1) x (1, 0, 0) in component "REFERENCE - v11 rubber contact pads"
  line L0 (17, 9.5) -> (33, 9.5)
  line L1 (35, 11.5) -> (35, 23.5)
  line L2 (33, 25.5) -> (17, 25.5)
  line L3 (15, 23.5) -> (15, 11.5)
  arc A0 (33, 9.5) -> (35, 11.5) centre (33, 11.5) ccw
  arc A1 (35, 23.5) -> (33, 25.5) centre (33, 23.5) ccw
  arc A2 (17, 25.5) -> (15, 23.5) centre (17, 23.5) ccw
  arc A3 (15, 11.5) -> (17, 9.5) centre (17, 11.5) ccw
extrude "Moving shoe rubber pad 25" add sketch "Moving shoe rubber pad 25 outline" along normal blind 2.5 separate body makes body 21 in component "REFERENCE - v11 rubber contact pads"
ref_plane "WorkPlane4" through (0, 0, 55) normal (0, 0, 1) x (1, 0, 0) in component "REFERENCE - v11 rubber contact pads"
sketch "Lower ledge pad 189 outline" plane through (0, 0, 55) normal (0, 0, 1) x (1, 0, 0) in component "REFERENCE - v11 rubber contact pads"
  line L0 (179, 0.5) -> (199, 0.5)
  line L1 (199, 0.5) -> (199, 10.5)
  line L2 (199, 10.5) -> (179, 10.5)
  line L3 (179, 10.5) -> (179, 0.5)
extrude "Lower ledge pad 189" add sketch "Lower ledge pad 189 outline" along normal blind 2.5 separate body makes body 22 in component "REFERENCE - v11 rubber contact pads"
ref_plane "WorkPlane5" through (0, 0, 67) normal (0, 0, 1) x (1, 0, 0) in component "REFERENCE - v11 rubber contact pads"
sketch "Upper ledge pad 189 outline" plane through (0, 0, 67) normal (0, 0, 1) x (1, 0, 0) in component "REFERENCE - v11 rubber contact pads"
  line L0 (179, 13) -> (199, 13)
  line L1 (199, 13) -> (199, 22)
  line L2 (199, 22) -> (179, 22)
  line L3 (179, 22) -> (179, 13)
extrude "Upper ledge pad 189" add sketch "Upper ledge pad 189 outline" along normal blind 2.5 separate body makes body 23 in component "REFERENCE - v11 rubber contact pads"
ref_plane "WorkPlane6" through (0, 0, -2.5) normal (0, 0, 1) x (1, 0, 0) in component "REFERENCE - v11 rubber contact pads"
sketch "Moving shoe rubber pad 189 outline" plane through (0, 0, -2.5) normal (0, 0, 1) x (1, 0, 0) in component "REFERENCE - v11 rubber contact pads"
  line L0 (181, 9.5) -> (197, 9.5)
  line L1 (199, 11.5) -> (199, 23.5)
  line L2 (197, 25.5) -> (181, 25.5)
  line L3 (179, 23.5) -> (179, 11.5)
  arc A0 (197, 9.5) -> (199, 11.5) centre (197, 11.5) ccw
  arc A1 (199, 23.5) -> (197, 25.5) centre (197, 23.5) ccw
  arc A2 (181, 25.5) -> (179, 23.5) centre (181, 23.5) ccw
  arc A3 (179, 11.5) -> (181, 9.5) centre (181, 11.5) ccw
extrude "Moving shoe rubber pad 189" add sketch "Moving shoe rubber pad 189 outline" along normal blind 2.5 separate body makes body 24 in component "REFERENCE - v11 rubber contact pads"
ref_plane "WorkPlane1" through (0, 0, -40) normal (0, 0, 1) x (1, 0, 0) in component "REFERENCE - M5 x 30 DIN 933 clamp bolts"
sketch "M5 hex head 25 outline" plane through (0, 0, -40) normal (0, 0, 1) x (1, 0, 0) in component "REFERENCE - M5 x 30 DIN 933 clamp bolts"
  line L0 (29.6188, 17.5) -> (27.3094, 21.5)
  line L1 (27.3094, 21.5) -> (22.6906, 21.5)
  line L2 (22.6906, 21.5) -> (20.3812, 17.5)
  line L3 (20.3812, 17.5) -> (22.6906, 13.5)
  line L4 (22.6906, 13.5) -> (27.3094, 13.5)
  line L5 (27.3094, 13.5) -> (29.6188, 17.5)
extrude "M5 hex head 25" add sketch "M5 hex head 25 outline" along normal blind 3.5 separate body makes body 25 in component "REFERENCE - M5 x 30 DIN 933 clamp bolts"
ref_plane "WorkPlane2" through (0, 0, -36.5) normal (0, 0, 1) x (1, 0, 0) in component "REFERENCE - M5 x 30 DIN 933 clamp bolts"
sketch "M5 full-thread envelope 25 layout" plane through (0, 0, -36.5) normal (0, 0, 1) x (1, 0, 0) in component "REFERENCE - M5 x 30 DIN 933 clamp bolts"
  circle A0 centre (25, 17.5) radius 2.5
extrude "M5 full-thread envelope 25" add sketch "M5 full-thread envelope 25 layout" along normal blind 30 bodies 25 in component "REFERENCE - M5 x 30 DIN 933 clamp bolts"
ref_plane "WorkPlane1" through (0, 0, -23.7) normal (0, 0, 1) x (1, 0, 0) in component "REFERENCE - M5 DIN 934 captive nuts"
sketch "M5 nut 25 outline" plane through (0, 0, -23.7) normal (0, 0, 1) x (1, 0, 0) in component "REFERENCE - M5 DIN 934 captive nuts"
  line L0 (29.6188, 17.5) -> (27.3094, 21.5)
  line L1 (27.3094, 21.5) -> (22.6906, 21.5)
  line L2 (22.6906, 21.5) -> (20.3812, 17.5)
  line L3 (20.3812, 17.5) -> (22.6906, 13.5)
  line L4 (22.6906, 13.5) -> (27.3094, 13.5)
  line L5 (27.3094, 13.5) -> (29.6188, 17.5)
extrude "M5 nut 25" add sketch "M5 nut 25 outline" along normal blind 4 separate body makes body 26 in component "REFERENCE - M5 DIN 934 captive nuts"
ref_plane "WorkPlane2" through (0, 0, -23.8) normal (0, 0, 1) x (1, 0, 0) in component "REFERENCE - M5 DIN 934 captive nuts"
sketch "M5 thread clearance envelope 25 layout" plane through (0, 0, -23.8) normal (0, 0, 1) x (1, 0, 0) in component "REFERENCE - M5 DIN 934 captive nuts"
  circle A0 centre (25, 17.5) radius 2.6
extrude "M5 thread clearance envelope 25" cut sketch "M5 thread clearance envelope 25 layout" along normal blind 4.2 bodies 26 in component "REFERENCE - M5 DIN 934 captive nuts"
ref_plane "WorkPlane3" through (0, 0, -40) normal (0, 0, 1) x (1, 0, 0) in component "REFERENCE - M5 x 30 DIN 933 clamp bolts"
sketch "M5 hex head 189 outline" plane through (0, 0, -40) normal (0, 0, 1) x (1, 0, 0) in component "REFERENCE - M5 x 30 DIN 933 clamp bolts"
  line L0 (193.6188, 17.5) -> (191.3094, 21.5)
  line L1 (191.3094, 21.5) -> (186.6906, 21.5)
  line L2 (186.6906, 21.5) -> (184.3812, 17.5)
  line L3 (184.3812, 17.5) -> (186.6906, 13.5)
  line L4 (186.6906, 13.5) -> (191.3094, 13.5)
  line L5 (191.3094, 13.5) -> (193.6188, 17.5)
extrude "M5 hex head 189" add sketch "M5 hex head 189 outline" along normal blind 3.5 separate body makes body 27 in component "REFERENCE - M5 x 30 DIN 933 clamp bolts"
ref_plane "WorkPlane4" through (0, 0, -36.5) normal (0, 0, 1) x (1, 0, 0) in component "REFERENCE - M5 x 30 DIN 933 clamp bolts"
sketch "M5 full-thread envelope 189 layout" plane through (0, 0, -36.5) normal (0, 0, 1) x (1, 0, 0) in component "REFERENCE - M5 x 30 DIN 933 clamp bolts"
  circle A0 centre (189, 17.5) radius 2.5
extrude "M5 full-thread envelope 189" add sketch "M5 full-thread envelope 189 layout" along normal blind 30 bodies 27 in component "REFERENCE - M5 x 30 DIN 933 clamp bolts"
ref_plane "WorkPlane3" through (0, 0, -23.7) normal (0, 0, 1) x (1, 0, 0) in component "REFERENCE - M5 DIN 934 captive nuts"
sketch "M5 nut 189 outline" plane through (0, 0, -23.7) normal (0, 0, 1) x (1, 0, 0) in component "REFERENCE - M5 DIN 934 captive nuts"
  line L0 (193.6188, 17.5) -> (191.3094, 21.5)
  line L1 (191.3094, 21.5) -> (186.6906, 21.5)
  line L2 (186.6906, 21.5) -> (184.3812, 17.5)
  line L3 (184.3812, 17.5) -> (186.6906, 13.5)
  line L4 (186.6906, 13.5) -> (191.3094, 13.5)
  line L5 (191.3094, 13.5) -> (193.6188, 17.5)
extrude "M5 nut 189" add sketch "M5 nut 189 outline" along normal blind 4 separate body makes body 28 in component "REFERENCE - M5 DIN 934 captive nuts"
ref_plane "WorkPlane4" through (0, 0, -23.8) normal (0, 0, 1) x (1, 0, 0) in component "REFERENCE - M5 DIN 934 captive nuts"
sketch "M5 thread clearance envelope 189 layout" plane through (0, 0, -23.8) normal (0, 0, 1) x (1, 0, 0) in component "REFERENCE - M5 DIN 934 captive nuts"
  circle A0 centre (189, 17.5) radius 2.6
extrude "M5 thread clearance envelope 189" cut sketch "M5 thread clearance envelope 189 layout" along normal blind 4.2 bodies 26 28 in component "REFERENCE - M5 DIN 934 captive nuts"
ref_plane "WorkPlane1" through (0, 0, 80.4) normal (0, 0, 1) x (1, 0, 0) in component "REFERENCE - six M3 x 10 button screws and washers"
sketch "M3 button head envelope (18, 16) layout" plane through (0, 0, 80.4) normal (0, 0, 1) x (1, 0, 0) in component "REFERENCE - six M3 x 10 button screws and washers"
  circle A0 centre (18, 16) radius 2.85
extrude "M3 button head envelope (18, 16)" add sketch "M3 button head envelope (18, 16) layout" along normal blind 1.65 separate body makes body 29 in component "REFERENCE - six M3 x 10 button screws and washers"
ref_plane "WorkPlane2" through (0, 0, 70.4) normal (0, 0, 1) x (1, 0, 0) in component "REFERENCE - six M3 x 10 button screws and washers"
sketch "M3 screw shaft (18, 16) layout" plane through (0, 0, 70.4) normal (0, 0, 1) x (1, 0, 0) in component "REFERENCE - six M3 x 10 button screws and washers"
  circle A0 centre (18, 16) radius 1.5
extrude "M3 screw shaft (18, 16)" add sketch "M3 screw shaft (18, 16) layout" along normal blind 10 bodies 29 in component "REFERENCE - six M3 x 10 button screws and washers"
ref_plane "WorkPlane3" through (0, 0, 79.9) normal (0, 0, 1) x (1, 0, 0) in component "REFERENCE - six M3 x 10 button screws and washers"
sketch "M3 washer OD (18, 16) layout" plane through (0, 0, 79.9) normal (0, 0, 1) x (1, 0, 0) in component "REFERENCE - six M3 x 10 button screws and washers"
  circle A0 centre (18, 16) radius 3.5
extrude "M3 washer OD (18, 16)" add sketch "M3 washer OD (18, 16) layout" along normal blind 0.5 bodies 29 in component "REFERENCE - six M3 x 10 button screws and washers"
ref_plane "WorkPlane1" through (0, 0, 71.1) normal (0, 0, 1) x (1, 0, 0) in component "REFERENCE - six M3 DIN 934 nuts"
sketch "M3 nut (18, 16) outline" plane through (0, 0, 71.1) normal (0, 0, 1) x (1, 0, 0) in component "REFERENCE - six M3 DIN 934 nuts"
  line L0 (21.1754, 16) -> (19.5877, 18.75)
  line L1 (19.5877, 18.75) -> (16.4123, 18.75)
  line L2 (16.4123, 18.75) -> (14.8246, 16)
  line L3 (14.8246, 16) -> (16.4123, 13.25)
  line L4 (16.4123, 13.25) -> (19.5877, 13.25)
  line L5 (19.5877, 13.25) -> (21.1754, 16)
extrude "M3 nut (18, 16)" add sketch "M3 nut (18, 16) outline" along normal blind 2.4 separate body makes body 30 in component "REFERENCE - six M3 DIN 934 nuts"
ref_plane "WorkPlane2" through (0, 0, 71) normal (0, 0, 1) x (1, 0, 0) in component "REFERENCE - six M3 DIN 934 nuts"
sketch "M3 thread clearance envelope (18, 16) layout" plane through (0, 0, 71) normal (0, 0, 1) x (1, 0, 0) in component "REFERENCE - six M3 DIN 934 nuts"
  circle A0 centre (18, 16) radius 1.6
extrude "M3 thread clearance envelope (18, 16)" cut sketch "M3 thread clearance envelope (18, 16) layout" along normal blind 2.6 bodies 30 in component "REFERENCE - six M3 DIN 934 nuts"
ref_plane "WorkPlane4" through (0, 0, 80.4) normal (0, 0, 1) x (1, 0, 0) in component "REFERENCE - six M3 x 10 button screws and washers"
sketch "M3 button head envelope (32, 16) layout" plane through (0, 0, 80.4) normal (0, 0, 1) x (1, 0, 0) in component "REFERENCE - six M3 x 10 button screws and washers"
  circle A0 centre (32, 16) radius 2.85
extrude "M3 button head envelope (32, 16)" add sketch "M3 button head envelope (32, 16) layout" along normal blind 1.65 separate body makes body 31 in component "REFERENCE - six M3 x 10 button screws and washers"
ref_plane "WorkPlane5" through (0, 0, 70.4) normal (0, 0, 1) x (1, 0, 0) in component "REFERENCE - six M3 x 10 button screws and washers"